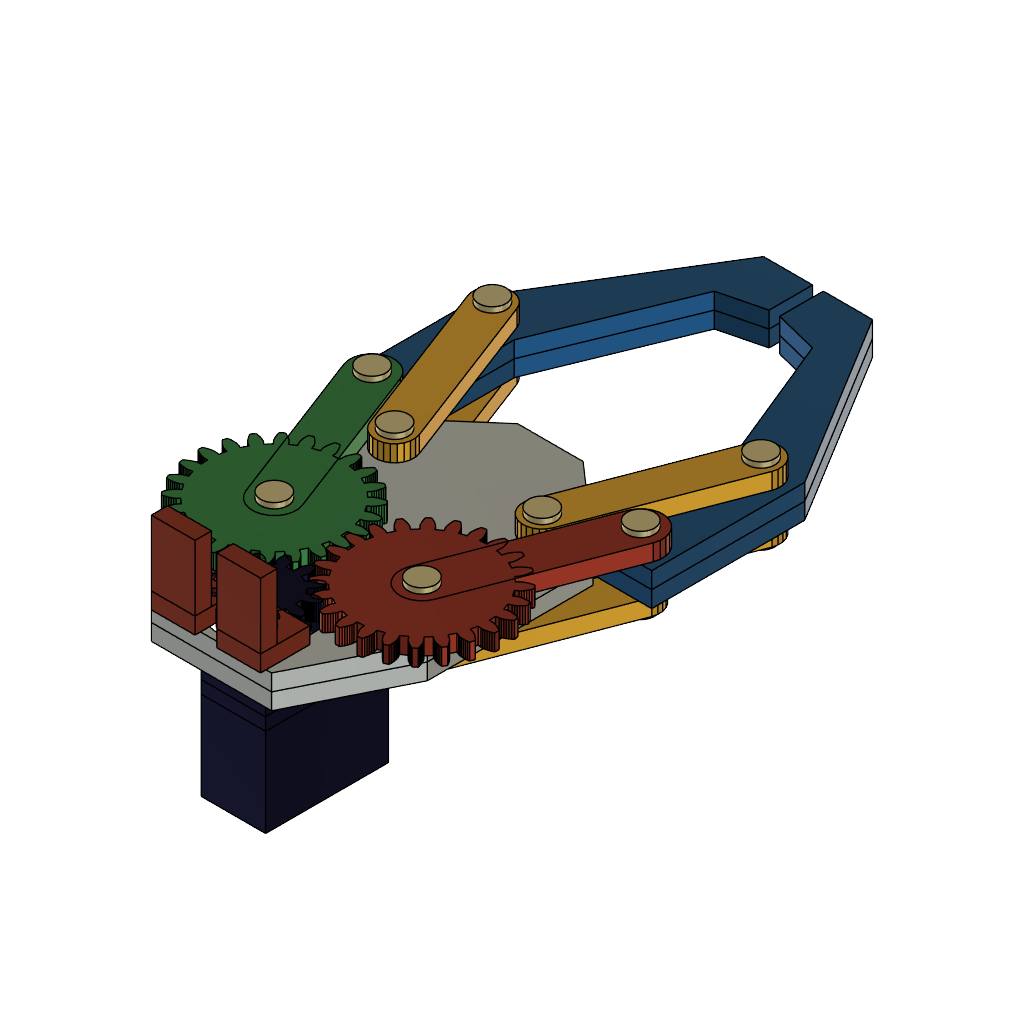
Robotic Gripper - SPARK PLUG recreation (Autodesk Fusion 360 design; units mm, degrees)
part number: 2026-11-17-09-29-30-338
part number: 2026-11-17-09-29-30-869
part number: 2026-11-17-09-29-32-026
part number: 2026-11-17-09-29-45-248
part number: 2026-11-17-09-29-48-497
part number: 2026-11-17-09-29-51-552
part number: 2026-11-17-09-29-54-288
part number: 2026-11-17-09-29-56-451
part number: 2026-11-17-09-29-59-617
part number: 2026-11-17-09-30-02-554
part number: 2026-11-17-09-30-05-354
part number: 2026-11-17-09-30-42-591
part number: 2026-11-17-09-30-51-417
part number: 2026-11-17-09-30-57-550
part number: 2026-11-17-09-31-01-790
part number: 2026-11-17-09-31-05-352
part number: 2026-11-17-09-31-09-246
part number: 2026-11-17-09-31-13-481
part number: 2026-11-17-09-31-18-259
part number: 2026-11-17-09-31-28-436
part number: 2026-11-17-09-31-31-446
part number: 2026-11-17-09-31-33-463
Autodesk Fusion 360 part; units mm, degrees
(part 1 of 3)
ref_plane "WorkPlane1" through (0, 0, -3) normal (0, 0, 1) x (1, 0, 0) in component "Frame - twin 3 mm plates"
sketch "Frame plate profile" plane through (0, 0, -3) normal (0, 0, 1) x (1, 0, 0) in component "Frame - twin 3 mm plates"
  line L0 (-11, -25) -> (11, -25)
  line L1 (11, -25) -> (20.5, -6)
  line L2 (20.5, -6) -> (20.5, 24.3)
  line L3 (20.5, 24.3) -> (6, 37)
  line L4 (6, 37) -> (-6, 37)
  line L5 (-6, 37) -> (-20.5, 24.3)
  line L6 (-20.5, 24.3) -> (-20.5, -6)
  line L7 (-20.5, -6) -> (-11, -25)
extrude "Frame plate" add sketch "Frame plate profile" along normal blind 3 makes body 1 in component "Frame - twin 3 mm plates"
sketch "Frame plate profile (1)" plane through (0, 0, 0) normal (0, 0, 1) x (1, 0, 0) in component "Frame - twin 3 mm plates"
  line L0 (-11, -25) -> (11, -25)
  line L1 (11, -25) -> (20.5, -6)
  line L2 (20.5, -6) -> (20.5, 24.3)
  line L3 (20.5, 24.3) -> (6, 37)
  line L4 (6, 37) -> (-6, 37)
  line L5 (-6, 37) -> (-20.5, 24.3)
  line L6 (-20.5, 24.3) -> (-20.5, -6)
  line L7 (-20.5, -6) -> (-11, -25)
extrude "Frame plate (1)" add sketch "Frame plate profile (1)" along normal blind 3 separate body makes body 2 in component "Frame - twin 3 mm plates"
ref_plane "WorkPlane2" through (0, 0, -3) normal (0, 0, 1) x (1, 0, 0) in component "Frame - twin 3 mm plates"
sketch "Pivot holes" plane through (0, 0, -3) normal (0, 0, 1) x (1, 0, 0) in component "Frame - twin 3 mm plates"
  circle A0 centre (-13.5, 0) radius 1.5
  circle A1 centre (13.5, 0) radius 1.5
  circle A2 centre (-13.5, 22) radius 1.5
  circle A3 centre (13.5, 22) radius 1.5
  circle A4 centre (-6, -21) radius 1.5
  circle A5 centre (6, -21) radius 1.5
extrude "Through holes" cut sketch "Pivot holes" along normal blind 6 bodies 1 2 in component "Frame - twin 3 mm plates"
ref_plane "WorkPlane3" through (0, 0, -3) normal (0, 0, 1) x (1, 0, 0) in component "Frame - twin 3 mm plates"
sketch "Motor clearance profile" plane through (0, 0, -3) normal (0, 0, 1) x (1, 0, 0) in component "Frame - twin 3 mm plates"
  circle A0 centre (0, -15.093) radius 8.5
extrude "Motor clearance" cut sketch "Motor clearance profile" along normal blind 6 bodies 1 2 in component "Frame - twin 3 mm plates"
ref_plane "WorkPlane1" through (0, 0, 3) normal (0, 0, 1) x (1, 0, 0) in component "Left 24T gear and crank"
sketch "24 tooth involute gear profile" plane through (0, 0, 3) normal (0, 0, 1) x (1, 0, 0) in component "Left 24T gear and crank"
  line L0 (-1.4453, -0.9707) -> (-0.8551, -1.0183)
  line L1 (-0.8551, -1.0183) -> (-0.5291, -0.995)
  line L2 (-0.5291, -0.995) -> (-0.2002, -0.9292)
  line L3 (-0.2002, -0.9292) -> (0.13, -0.8336)
  line L4 (0.13, -0.8336) -> (0.4604, -0.7126)
  line L5 (0.4604, -0.7126) -> (0.7905, -0.5684)
  line L6 (0.7905, -0.5684) -> (1.1195, -0.4024)
  line L7 (1.1195, -0.4024) -> (1.1195, 0.4024)
  line L8 (1.1195, 0.4024) -> (0.7905, 0.5684)
  line L9 (0.7905, 0.5684) -> (0.4604, 0.7126)
  line L10 (0.4604, 0.7126) -> (0.13, 0.8336)
  line L11 (0.13, 0.8336) -> (-0.2002, 0.9292)
  line L12 (-0.2002, 0.9292) -> (-0.5291, 0.995)
  line L13 (-0.5291, 0.995) -> (-0.8551, 1.0183)
  line L14 (-0.8551, 1.0183) -> (-1.4453, 0.9707)
  line L15 (-1.4453, 0.9707) -> (-1.6048, 2.1823)
  line L16 (-1.6048, 2.1823) -> (-1.0224, 2.2892)
  line L17 (-1.0224, 2.2892) -> (-0.7135, 2.396)
  line L18 (-0.7135, 2.396) -> (-0.4129, 2.5447)
  line L19 (-0.4129, 2.5447) -> (-0.1187, 2.7225)
  line L20 (-0.1187, 2.7225) -> (0.1692, 2.9249)
  line L21 (0.1692, 2.9249) -> (0.4507, 3.1496)
  line L22 (0.4507, 3.1496) -> (0.7255, 3.3951)
  line L23 (0.7255, 3.3951) -> (0.5172, 4.1725)
  line L24 (0.5172, 4.1725) -> (0.1565, 4.2477)
  line L25 (0.1565, 4.2477) -> (-0.1997, 4.3015)
  line L26 (-0.1997, 4.3015) -> (-0.5502, 4.3329)
  line L27 (-0.5502, 4.3329) -> (-0.8939, 4.3398)
  line L28 (-0.8939, 4.3398) -> (-1.2286, 4.3183)
  line L29 (-1.2286, 4.3183) -> (-1.5495, 4.2563)
  line L30 (-1.5495, 4.2563) -> (-2.1073, 4.0577)
  line L31 (-2.1073, 4.0577) -> (-2.5749, 5.1867)
  line L32 (-2.5749, 5.1867) -> (-2.04, 5.4406)
  line L33 (-2.04, 5.4406) -> (-1.7693, 5.6237)
  line L34 (-1.7693, 5.6237) -> (-1.5174, 5.8452)
  line L35 (-1.5174, 5.8452) -> (-1.2793, 6.093)
  line L36 (-1.2793, 6.093) -> (-1.0536, 6.3631)
  line L37 (-1.0536, 6.3631) -> (-0.8399, 6.653)
  line L38 (-0.8399, 6.653) -> (-0.638, 6.9612)
  line L39 (-0.638, 6.9612) -> (-1.0404, 7.6583)
  line L40 (-1.0404, 7.6583) -> (-1.4082, 7.6375)
  line L41 (-1.4082, 7.6375) -> (-1.7662, 7.5973)
  line L42 (-1.7662, 7.5973) -> (-2.1129, 7.5369)
  line L43 (-2.1129, 7.5369) -> (-2.4466, 7.4546)
  line L44 (-2.4466, 7.4546) -> (-2.7644, 7.3472)
  line L45 (-2.7644, 7.3472) -> (-3.0583, 7.2043)
  line L46 (-3.0583, 7.2043) -> (-3.5457, 6.868)
  line L47 (-3.5457, 6.868) -> (-4.2896, 7.8376)
  line L48 (-4.2896, 7.8376) -> (-3.8387, 8.2213)
  line L49 (-3.8387, 8.2213) -> (-3.6246, 8.4682)
  line L50 (-3.6246, 8.4682) -> (-3.4386, 8.7474)
  line L51 (-3.4386, 8.7474) -> (-3.2727, 9.0484)
  line L52 (-3.2727, 9.0484) -> (-3.1246, 9.3676)
  line L53 (-3.1246, 9.3676) -> (-2.9932, 9.703)
  line L54 (-2.9932, 9.703) -> (-2.8779, 10.0529)
  line L55 (-2.8779, 10.0529) -> (-3.4471, 10.6221)
  line L56 (-3.4471, 10.6221) -> (-3.797, 10.5068)
  line L57 (-3.797, 10.5068) -> (-4.1324, 10.3754)
  line L58 (-4.1324, 10.3754) -> (-4.4516, 10.2273)
  line L59 (-4.4516, 10.2273) -> (-4.7526, 10.0614)
  line L60 (-4.7526, 10.0614) -> (-5.0318, 9.8754)
  line L61 (-5.0318, 9.8754) -> (-5.2787, 9.6613)
  line L62 (-5.2787, 9.6613) -> (-5.6624, 9.2104)
  line L63 (-5.6624, 9.2104) -> (-6.632, 9.9543)
  line L64 (-6.632, 9.9543) -> (-6.2957, 10.4417)
  line L65 (-6.2957, 10.4417) -> (-6.1528, 10.7356)
  line L66 (-6.1528, 10.7356) -> (-6.0454, 11.0534)
  line L67 (-6.0454, 11.0534) -> (-5.9631, 11.3871)
  line L68 (-5.9631, 11.3871) -> (-5.9027, 11.7338)
  line L69 (-5.9027, 11.7338) -> (-5.8625, 12.0918)
  line L70 (-5.8625, 12.0918) -> (-5.8417, 12.4596)
  line L71 (-5.8417, 12.4596) -> (-6.5388, 12.862)
  line L72 (-6.5388, 12.862) -> (-6.847, 12.6601)
  line L73 (-6.847, 12.6601) -> (-7.1369, 12.4464)
  line L74 (-7.1369, 12.4464) -> (-7.407, 12.2207)
  line L75 (-7.407, 12.2207) -> (-7.6548, 11.9826)
  line L76 (-7.6548, 11.9826) -> (-7.8763, 11.7307)
  line L77 (-7.8763, 11.7307) -> (-8.0594, 11.46)
  line L78 (-8.0594, 11.46) -> (-8.3133, 10.9251)
  line L79 (-8.3133, 10.9251) -> (-9.4423, 11.3927)
  line L80 (-9.4423, 11.3927) -> (-9.2437, 11.9505)
  line L81 (-9.2437, 11.9505) -> (-9.1817, 12.2714)
  line L82 (-9.1817, 12.2714) -> (-9.1602, 12.6061)
  line L83 (-9.1602, 12.6061) -> (-9.1671, 12.9498)
  line L84 (-9.1671, 12.9498) -> (-9.1985, 13.3003)
  line L85 (-9.1985, 13.3003) -> (-9.2523, 13.6565)
  line L86 (-9.2523, 13.6565) -> (-9.3275, 14.0172)
  line L87 (-9.3275, 14.0172) -> (-10.1049, 14.2255)
  line L88 (-10.1049, 14.2255) -> (-10.3504, 13.9507)
  line L89 (-10.3504, 13.9507) -> (-10.5751, 13.6692)
  line L90 (-10.5751, 13.6692) -> (-10.7775, 13.3813)
  line L91 (-10.7775, 13.3813) -> (-10.9553, 13.0871)
  line L92 (-10.9553, 13.0871) -> (-11.104, 12.7865)
  line L93 (-11.104, 12.7865) -> (-11.2108, 12.4776)
  line L94 (-11.2108, 12.4776) -> (-11.3177, 11.8952)
  line L95 (-11.3177, 11.8952) -> (-12.5293, 12.0547)
  line L96 (-12.5293, 12.0547) -> (-12.4817, 12.6449)
  line L97 (-12.4817, 12.6449) -> (-12.505, 12.9709)
  line L98 (-12.505, 12.9709) -> (-12.5708, 13.2998)
  line L99 (-12.5708, 13.2998) -> (-12.6664, 13.63)
  line L100 (-12.6664, 13.63) -> (-12.7874, 13.9604)
  line L101 (-12.7874, 13.9604) -> (-12.9316, 14.2905)
  line L102 (-12.9316, 14.2905) -> (-13.0976, 14.6195)
  line L103 (-13.0976, 14.6195) -> (-13.9024, 14.6195)
  line L104 (-13.9024, 14.6195) -> (-14.0684, 14.2905)
  line L105 (-14.0684, 14.2905) -> (-14.2126, 13.9604)
  line L106 (-14.2126, 13.9604) -> (-14.3336, 13.63)
  line L107 (-14.3336, 13.63) -> (-14.4292, 13.2998)
  line L108 (-14.4292, 13.2998) -> (-14.495, 12.9709)
  line L109 (-14.495, 12.9709) -> (-14.5183, 12.6449)
  line L110 (-14.5183, 12.6449) -> (-14.4707, 12.0547)
  line L111 (-14.4707, 12.0547) -> (-15.6823, 11.8952)
  line L112 (-15.6823, 11.8952) -> (-15.7892, 12.4776)
  line L113 (-15.7892, 12.4776) -> (-15.896, 12.7865)
  line L114 (-15.896, 12.7865) -> (-16.0447, 13.0871)
  line L115 (-16.0447, 13.0871) -> (-16.2225, 13.3813)
  line L116 (-16.2225, 13.3813) -> (-16.4249, 13.6692)
  line L117 (-16.4249, 13.6692) -> (-16.6496, 13.9507)
  line L118 (-16.6496, 13.9507) -> (-16.8951, 14.2255)
  line L119 (-16.8951, 14.2255) -> (-17.6725, 14.0172)
  line L120 (-17.6725, 14.0172) -> (-17.7477, 13.6565)
  line L121 (-17.7477, 13.6565) -> (-17.8015, 13.3003)
  line L122 (-17.8015, 13.3003) -> (-17.8329, 12.9498)
  line L123 (-17.8329, 12.9498) -> (-17.8398, 12.6061)
  line L124 (-17.8398, 12.6061) -> (-17.8183, 12.2714)
  line L125 (-17.8183, 12.2714) -> (-17.7563, 11.9505)
  line L126 (-17.7563, 11.9505) -> (-17.5577, 11.3927)
  line L127 (-17.5577, 11.3927) -> (-18.6867, 10.9251)
  line L128 (-18.6867, 10.9251) -> (-18.9406, 11.46)
  line L129 (-18.9406, 11.46) -> (-19.1237, 11.7307)
  line L130 (-19.1237, 11.7307) -> (-19.3452, 11.9826)
  line L131 (-19.3452, 11.9826) -> (-19.593, 12.2207)
  line L132 (-19.593, 12.2207) -> (-19.8631, 12.4464)
  line L133 (-19.8631, 12.4464) -> (-20.153, 12.6601)
  line L134 (-20.153, 12.6601) -> (-20.4612, 12.862)
  line L135 (-20.4612, 12.862) -> (-21.1583, 12.4596)
  line L136 (-21.1583, 12.4596) -> (-21.1375, 12.0918)
  line L137 (-21.1375, 12.0918) -> (-21.0973, 11.7338)
  line L138 (-21.0973, 11.7338) -> (-21.0369, 11.3871)
  line L139 (-21.0369, 11.3871) -> (-20.9546, 11.0534)
  line L140 (-20.9546, 11.0534) -> (-20.8472, 10.7356)
  line L141 (-20.8472, 10.7356) -> (-20.7043, 10.4417)
  line L142 (-20.7043, 10.4417) -> (-20.368, 9.9543)
  line L143 (-20.368, 9.9543) -> (-21.3376, 9.2104)
  line L144 (-21.3376, 9.2104) -> (-21.7213, 9.6613)
  line L145 (-21.7213, 9.6613) -> (-21.9682, 9.8754)
  line L146 (-21.9682, 9.8754) -> (-22.2474, 10.0614)
  line L147 (-22.2474, 10.0614) -> (-22.5484, 10.2273)
  line L148 (-22.5484, 10.2273) -> (-22.8676, 10.3754)
  line L149 (-22.8676, 10.3754) -> (-23.203, 10.5068)
  line L150 (-23.203, 10.5068) -> (-23.5529, 10.6221)
  line L151 (-23.5529, 10.6221) -> (-24.1221, 10.0529)
  line L152 (-24.1221, 10.0529) -> (-24.0068, 9.703)
  line L153 (-24.0068, 9.703) -> (-23.8754, 9.3676)
  line L154 (-23.8754, 9.3676) -> (-23.7273, 9.0484)
  line L155 (-23.7273, 9.0484) -> (-23.5614, 8.7474)
  line L156 (-23.5614, 8.7474) -> (-23.3754, 8.4682)
  line L157 (-23.3754, 8.4682) -> (-23.1613, 8.2213)
  line L158 (-23.1613, 8.2213) -> (-22.7104, 7.8376)
  line L159 (-22.7104, 7.8376) -> (-23.4543, 6.868)
  line L160 (-23.4543, 6.868) -> (-23.9417, 7.2043)
  line L161 (-23.9417, 7.2043) -> (-24.2356, 7.3472)
  line L162 (-24.2356, 7.3472) -> (-24.5534, 7.4546)
  line L163 (-24.5534, 7.4546) -> (-24.8871, 7.5369)
  line L164 (-24.8871, 7.5369) -> (-25.2338, 7.5973)
  line L165 (-25.2338, 7.5973) -> (-25.5918, 7.6375)
  line L166 (-25.5918, 7.6375) -> (-25.9596, 7.6583)
  line L167 (-25.9596, 7.6583) -> (-26.362, 6.9612)
  line L168 (-26.362, 6.9612) -> (-26.1601, 6.653)
  line L169 (-26.1601, 6.653) -> (-25.9464, 6.3631)
  line L170 (-25.9464, 6.3631) -> (-25.7207, 6.093)
  line L171 (-25.7207, 6.093) -> (-25.4826, 5.8452)
  line L172 (-25.4826, 5.8452) -> (-25.2307, 5.6237)
  line L173 (-25.2307, 5.6237) -> (-24.96, 5.4406)
  line L174 (-24.96, 5.4406) -> (-24.4251, 5.1867)
  line L175 (-24.4251, 5.1867) -> (-24.8927, 4.0577)
  line L176 (-24.8927, 4.0577) -> (-25.4505, 4.2563)
  line L177 (-25.4505, 4.2563) -> (-25.7714, 4.3183)
  line L178 (-25.7714, 4.3183) -> (-26.1061, 4.3398)
  line L179 (-26.1061, 4.3398) -> (-26.4498, 4.3329)
  line L180 (-26.4498, 4.3329) -> (-26.8003, 4.3015)
  line L181 (-26.8003, 4.3015) -> (-27.1565, 4.2477)
  line L182 (-27.1565, 4.2477) -> (-27.5172, 4.1725)
  line L183 (-27.5172, 4.1725) -> (-27.7255, 3.3951)
  line L184 (-27.7255, 3.3951) -> (-27.4507, 3.1496)
  line L185 (-27.4507, 3.1496) -> (-27.1692, 2.9249)
  line L186 (-27.1692, 2.9249) -> (-26.8813, 2.7225)
  line L187 (-26.8813, 2.7225) -> (-26.5871, 2.5447)
  line L188 (-26.5871, 2.5447) -> (-26.2865, 2.396)
  line L189 (-26.2865, 2.396) -> (-25.9776, 2.2892)
  line L190 (-25.9776, 2.2892) -> (-25.3952, 2.1823)
  line L191 (-25.3952, 2.1823) -> (-25.5547, 0.9707)
  line L192 (-25.5547, 0.9707) -> (-26.1449, 1.0183)
  line L193 (-26.1449, 1.0183) -> (-26.4709, 0.995)
  line L194 (-26.4709, 0.995) -> (-26.7998, 0.9292)
  line L195 (-26.7998, 0.9292) -> (-27.13, 0.8336)
  line L196 (-27.13, 0.8336) -> (-27.4604, 0.7126)
  line L197 (-27.4604, 0.7126) -> (-27.7905, 0.5684)
  line L198 (-27.7905, 0.5684) -> (-28.1195, 0.4024)
  line L199 (-28.1195, 0.4024) -> (-28.1195, -0.4024)
  line L200 (-28.1195, -0.4024) -> (-27.7905, -0.5684)
  line L201 (-27.7905, -0.5684) -> (-27.4604, -0.7126)
  line L202 (-27.4604, -0.7126) -> (-27.13, -0.8336)
  line L203 (-27.13, -0.8336) -> (-26.7998, -0.9292)
  line L204 (-26.7998, -0.9292) -> (-26.4709, -0.995)
  line L205 (-26.4709, -0.995) -> (-26.1449, -1.0183)
  line L206 (-26.1449, -1.0183) -> (-25.5547, -0.9707)
  line L207 (-25.5547, -0.9707) -> (-25.3952, -2.1823)
  line L208 (-25.3952, -2.1823) -> (-25.9776, -2.2892)
  line L209 (-25.9776, -2.2892) -> (-26.2865, -2.396)
  line L210 (-26.2865, -2.396) -> (-26.5871, -2.5447)
  line L211 (-26.5871, -2.5447) -> (-26.8813, -2.7225)
  line L212 (-26.8813, -2.7225) -> (-27.1692, -2.9249)
  line L213 (-27.1692, -2.9249) -> (-27.4507, -3.1496)
  line L214 (-27.4507, -3.1496) -> (-27.7255, -3.3951)
  line L215 (-27.7255, -3.3951) -> (-27.5172, -4.1725)
  line L216 (-27.5172, -4.1725) -> (-27.1565, -4.2477)
  line L217 (-27.1565, -4.2477) -> (-26.8003, -4.3015)
  line L218 (-26.8003, -4.3015) -> (-26.4498, -4.3329)
  line L219 (-26.4498, -4.3329) -> (-26.1061, -4.3398)
  line L220 (-26.1061, -4.3398) -> (-25.7714, -4.3183)
  line L221 (-25.7714, -4.3183) -> (-25.4505, -4.2563)
  line L222 (-25.4505, -4.2563) -> (-24.8927, -4.0577)
  line L223 (-24.8927, -4.0577) -> (-24.4251, -5.1867)
  line L224 (-24.4251, -5.1867) -> (-24.96, -5.4406)
  line L225 (-24.96, -5.4406) -> (-25.2307, -5.6237)
  line L226 (-25.2307, -5.6237) -> (-25.4826, -5.8452)
  line L227 (-25.4826, -5.8452) -> (-25.7207, -6.093)
  line L228 (-25.7207, -6.093) -> (-25.9464, -6.3631)
  line L229 (-25.9464, -6.3631) -> (-26.1601, -6.653)
  line L230 (-26.1601, -6.653) -> (-26.362, -6.9612)
  line L231 (-26.362, -6.9612) -> (-25.9596, -7.6583)
  line L232 (-25.9596, -7.6583) -> (-25.5918, -7.6375)
  line L233 (-25.5918, -7.6375) -> (-25.2338, -7.5973)
  line L234 (-25.2338, -7.5973) -> (-24.8871, -7.5369)
  line L235 (-24.8871, -7.5369) -> (-24.5534, -7.4546)
  line L236 (-24.5534, -7.4546) -> (-24.2356, -7.3472)
  line L237 (-24.2356, -7.3472) -> (-23.9417, -7.2043)
  line L238 (-23.9417, -7.2043) -> (-23.4543, -6.868)
  line L239 (-23.4543, -6.868) -> (-22.7104, -7.8376)
  line L240 (-22.7104, -7.8376) -> (-23.1613, -8.2213)
  line L241 (-23.1613, -8.2213) -> (-23.3754, -8.4682)
  line L242 (-23.3754, -8.4682) -> (-23.5614, -8.7474)
  line L243 (-23.5614, -8.7474) -> (-23.7273, -9.0484)
  line L244 (-23.7273, -9.0484) -> (-23.8754, -9.3676)
  line L245 (-23.8754, -9.3676) -> (-24.0068, -9.703)
  line L246 (-24.0068, -9.703) -> (-24.1221, -10.0529)
  line L247 (-24.1221, -10.0529) -> (-23.5529, -10.6221)
  line L248 (-23.5529, -10.6221) -> (-23.203, -10.5068)
  line L249 (-23.203, -10.5068) -> (-22.8676, -10.3754)
  line L250 (-22.8676, -10.3754) -> (-22.5484, -10.2273)
  line L251 (-22.5484, -10.2273) -> (-22.2474, -10.0614)
  line L252 (-22.2474, -10.0614) -> (-21.9682, -9.8754)
  line L253 (-21.9682, -9.8754) -> (-21.7213, -9.6613)
  line L254 (-21.7213, -9.6613) -> (-21.3376, -9.2104)
  line L255 (-21.3376, -9.2104) -> (-20.368, -9.9543)
  line L256 (-20.368, -9.9543) -> (-20.7043, -10.4417)
  line L257 (-20.7043, -10.4417) -> (-20.8472, -10.7356)
  line L258 (-20.8472, -10.7356) -> (-20.9546, -11.0534)
  line L259 (-20.9546, -11.0534) -> (-21.0369, -11.3871)
  line L260 (-21.0369, -11.3871) -> (-21.0973, -11.7338)
  line L261 (-21.0973, -11.7338) -> (-21.1375, -12.0918)
  line L262 (-21.1375, -12.0918) -> (-21.1583, -12.4596)
  line L263 (-21.1583, -12.4596) -> (-20.4612, -12.862)
  line L264 (-20.4612, -12.862) -> (-20.153, -12.6601)
  line L265 (-20.153, -12.6601) -> (-19.8631, -12.4464)
  line L266 (-19.8631, -12.4464) -> (-19.593, -12.2207)
  line L267 (-19.593, -12.2207) -> (-19.3452, -11.9826)
  line L268 (-19.3452, -11.9826) -> (-19.1237, -11.7307)
  line L269 (-19.1237, -11.7307) -> (-18.9406, -11.46)
  line L270 (-18.9406, -11.46) -> (-18.6867, -10.9251)
  line L271 (-18.6867, -10.9251) -> (-17.5577, -11.3927)
  line L272 (-17.5577, -11.3927) -> (-17.7563, -11.9505)
  line L273 (-17.7563, -11.9505) -> (-17.8183, -12.2714)
  line L274 (-17.8183, -12.2714) -> (-17.8398, -12.6061)
  line L275 (-17.8398, -12.6061) -> (-17.8329, -12.9498)
  line L276 (-17.8329, -12.9498) -> (-17.8015, -13.3003)
  line L277 (-17.8015, -13.3003) -> (-17.7477, -13.6565)
  line L278 (-17.7477, -13.6565) -> (-17.6725, -14.0172)
  line L279 (-17.6725, -14.0172) -> (-16.8951, -14.2255)
  line L280 (-16.8951, -14.2255) -> (-16.6496, -13.9507)
  line L281 (-16.6496, -13.9507) -> (-16.4249, -13.6692)
  line L282 (-16.4249, -13.6692) -> (-16.2225, -13.3813)
  line L283 (-16.2225, -13.3813) -> (-16.0447, -13.0871)
  line L284 (-16.0447, -13.0871) -> (-15.896, -12.7865)
  line L285 (-15.896, -12.7865) -> (-15.7892, -12.4776)
  line L286 (-15.7892, -12.4776) -> (-15.6823, -11.8952)
  line L287 (-15.6823, -11.8952) -> (-14.4707, -12.0547)
  line L288 (-14.4707, -12.0547) -> (-14.5183, -12.6449)
  line L289 (-14.5183, -12.6449) -> (-14.495, -12.9709)
  line L290 (-14.495, -12.9709) -> (-14.4292, -13.2998)
  line L291 (-14.4292, -13.2998) -> (-14.3336, -13.63)
  line L292 (-14.3336, -13.63) -> (-14.2126, -13.9604)
  line L293 (-14.2126, -13.9604) -> (-14.0684, -14.2905)
  line L294 (-14.0684, -14.2905) -> (-13.9024, -14.6195)
  line L295 (-13.9024, -14.6195) -> (-13.0976, -14.6195)
  line L296 (-13.0976, -14.6195) -> (-12.9316, -14.2905)
  line L297 (-12.9316, -14.2905) -> (-12.7874, -13.9604)
  line L298 (-12.7874, -13.9604) -> (-12.6664, -13.63)
  line L299 (-12.6664, -13.63) -> (-12.5708, -13.2998)
  line L300 (-12.5708, -13.2998) -> (-12.505, -12.9709)
  line L301 (-12.505, -12.9709) -> (-12.4817, -12.6449)
  line L302 (-12.4817, -12.6449) -> (-12.5293, -12.0547)
  line L303 (-12.5293, -12.0547) -> (-11.3177, -11.8952)
  line L304 (-11.3177, -11.8952) -> (-11.2108, -12.4776)
  line L305 (-11.2108, -12.4776) -> (-11.104, -12.7865)
  line L306 (-11.104, -12.7865) -> (-10.9553, -13.0871)
  line L307 (-10.9553, -13.0871) -> (-10.7775, -13.3813)
  line L308 (-10.7775, -13.3813) -> (-10.5751, -13.6692)
  line L309 (-10.5751, -13.6692) -> (-10.3504, -13.9507)
  line L310 (-10.3504, -13.9507) -> (-10.1049, -14.2255)
  line L311 (-10.1049, -14.2255) -> (-9.3275, -14.0172)
  line L312 (-9.3275, -14.0172) -> (-9.2523, -13.6565)
  line L313 (-9.2523, -13.6565) -> (-9.1985, -13.3003)
  line L314 (-9.1985, -13.3003) -> (-9.1671, -12.9498)
  line L315 (-9.1671, -12.9498) -> (-9.1602, -12.6061)
  line L316 (-9.1602, -12.6061) -> (-9.1817, -12.2714)
  line L317 (-9.1817, -12.2714) -> (-9.2437, -11.9505)
  line L318 (-9.2437, -11.9505) -> (-9.4423, -11.3927)
  line L319 (-9.4423, -11.3927) -> (-8.3133, -10.9251)
  line L320 (-8.3133, -10.9251) -> (-8.0594, -11.46)
  line L321 (-8.0594, -11.46) -> (-7.8763, -11.7307)
  line L322 (-7.8763, -11.7307) -> (-7.6548, -11.9826)
  line L323 (-7.6548, -11.9826) -> (-7.407, -12.2207)
  line L324 (-7.407, -12.2207) -> (-7.1369, -12.4464)
  line L325 (-7.1369, -12.4464) -> (-6.847, -12.6601)
  line L326 (-6.847, -12.6601) -> (-6.5388, -12.862)
  line L327 (-6.5388, -12.862) -> (-5.8417, -12.4596)
  line L328 (-5.8417, -12.4596) -> (-5.8625, -12.0918)
  line L329 (-5.8625, -12.0918) -> (-5.9027, -11.7338)
  line L330 (-5.9027, -11.7338) -> (-5.9631, -11.3871)
  line L331 (-5.9631, -11.3871) -> (-6.0454, -11.0534)
  line L332 (-6.0454, -11.0534) -> (-6.1528, -10.7356)
  line L333 (-6.1528, -10.7356) -> (-6.2957, -10.4417)
  line L334 (-6.2957, -10.4417) -> (-6.632, -9.9543)
  line L335 (-6.632, -9.9543) -> (-5.6624, -9.2104)
  line L336 (-5.6624, -9.2104) -> (-5.2787, -9.6613)
  line L337 (-5.2787, -9.6613) -> (-5.0318, -9.8754)
  line L338 (-5.0318, -9.8754) -> (-4.7526, -10.0614)
  line L339 (-4.7526, -10.0614) -> (-4.4516, -10.2273)
  line L340 (-4.4516, -10.2273) -> (-4.1324, -10.3754)
  line L341 (-4.1324, -10.3754) -> (-3.797, -10.5068)
  line L342 (-3.797, -10.5068) -> (-3.4471, -10.6221)
  line L343 (-3.4471, -10.6221) -> (-2.8779, -10.0529)
  line L344 (-2.8779, -10.0529) -> (-2.9932, -9.703)
  line L345 (-2.9932, -9.703) -> (-3.1246, -9.3676)
  line L346 (-3.1246, -9.3676) -> (-3.2727, -9.0484)
  line L347 (-3.2727, -9.0484) -> (-3.4386, -8.7474)
  line L348 (-3.4386, -8.7474) -> (-3.6246, -8.4682)
  line L349 (-3.6246, -8.4682) -> (-3.8387, -8.2213)
  line L350 (-3.8387, -8.2213) -> (-4.2896, -7.8376)
  line L351 (-4.2896, -7.8376) -> (-3.5457, -6.868)
  line L352 (-3.5457, -6.868) -> (-3.0583, -7.2043)
  line L353 (-3.0583, -7.2043) -> (-2.7644, -7.3472)
  line L354 (-2.7644, -7.3472) -> (-2.4466, -7.4546)
  line L355 (-2.4466, -7.4546) -> (-2.1129, -7.5369)
  line L356 (-2.1129, -7.5369) -> (-1.7662, -7.5973)
  line L357 (-1.7662, -7.5973) -> (-1.4082, -7.6375)
  line L358 (-1.4082, -7.6375) -> (-1.0404, -7.6583)
  line L359 (-1.0404, -7.6583) -> (-0.638, -6.9612)
  line L360 (-0.638, -6.9612) -> (-0.8399, -6.653)
  line L361 (-0.8399, -6.653) -> (-1.0536, -6.3631)
  line L362 (-1.0536, -6.3631) -> (-1.2793, -6.093)
  line L363 (-1.2793, -6.093) -> (-1.5174, -5.8452)
  line L364 (-1.5174, -5.8452) -> (-1.7693, -5.6237)
  line L365 (-1.7693, -5.6237) -> (-2.04, -5.4406)
  line L366 (-2.04, -5.4406) -> (-2.5749, -5.1867)
  line L367 (-2.5749, -5.1867) -> (-2.1073, -4.0577)
  line L368 (-2.1073, -4.0577) -> (-1.5495, -4.2563)
  line L369 (-1.5495, -4.2563) -> (-1.2286, -4.3183)
  line L370 (-1.2286, -4.3183) -> (-0.8939, -4.3398)
  line L371 (-0.8939, -4.3398) -> (-0.5502, -4.3329)
  line L372 (-0.5502, -4.3329) -> (-0.1997, -4.3015)
  line L373 (-0.1997, -4.3015) -> (0.1565, -4.2477)
  line L374 (0.1565, -4.2477) -> (0.5172, -4.1725)
  line L375 (0.5172, -4.1725) -> (0.7255, -3.3951)
  line L376 (0.7255, -3.3951) -> (0.4507, -3.1496)
  line L377 (0.4507, -3.1496) -> (0.1692, -2.9249)
  line L378 (0.1692, -2.9249) -> (-0.1187, -2.7225)
  line L379 (-0.1187, -2.7225) -> (-0.4129, -2.5447)
  line L380 (-0.4129, -2.5447) -> (-0.7135, -2.396)
  line L381 (-0.7135, -2.396) -> (-1.0224, -2.2892)
  line L382 (-1.0224, -2.2892) -> (-1.6048, -2.1823)
  line L383 (-1.6048, -2.1823) -> (-1.4453, -0.9707)
extrude "24 tooth involute gear" add sketch "24 tooth involute gear profile" along normal blind 3 separate body makes body 3 in component "Left 24T gear and crank"
ref_plane "WorkPlane2" through (0, 0, 3) normal (0, 0, 1) x (1, 0, 0) in component "Left 24T gear and crank"
sketch "31 mm crank profile" plane through (0, 0, 3) normal (0, 0, 1) x (1, 0, 0) in component "Left 24T gear and crank"
  line L0 (-22.9759, 29.786) -> (-23.537, 30.6667)
  line L1 (-23.537, 30.6667) -> (-24.3069, 31.3721)
  line L2 (-24.3069, 31.3721) -> (-25.2331, 31.8543)
  line L3 (-25.2331, 31.8543) -> (-26.2525, 32.0803)
  line L4 (-26.2525, 32.0803) -> (-27.2958, 32.0348)
  line L5 (-27.2958, 32.0348) -> (-28.2916, 31.7208)
  line L6 (-28.2916, 31.7208) -> (-29.1723, 31.1597)
  line L7 (-29.1723, 31.1597) -> (-29.8778, 30.3898)
  line L8 (-29.8778, 30.3898) -> (-30.3599, 29.4636)
  line L9 (-30.3599, 29.4636) -> (-30.5859, 28.4442)
  line L10 (-30.5859, 28.4442) -> (-30.5404, 27.4009)
  line L11 (-30.5404, 27.4009) -> (-30.2264, 26.4051)
  line L12 (-30.2264, 26.4051) -> (-17.1252, -1.6905)
  line L13 (-17.1252, -1.6905) -> (-16.5642, -2.5712)
  line L14 (-16.5642, -2.5712) -> (-15.7943, -3.2766)
  line L15 (-15.7943, -3.2766) -> (-14.8681, -3.7588)
  line L16 (-14.8681, -3.7588) -> (-13.8486, -3.9848)
  line L17 (-13.8486, -3.9848) -> (-12.8054, -3.9392)
  line L18 (-12.8054, -3.9392) -> (-11.8095, -3.6252)
  line L19 (-11.8095, -3.6252) -> (-10.9288, -3.0642)
  line L20 (-10.9288, -3.0642) -> (-10.2234, -2.2943)
  line L21 (-10.2234, -2.2943) -> (-9.7412, -1.3681)
  line L22 (-9.7412, -1.3681) -> (-9.5152, -0.3486)
  line L23 (-9.5152, -0.3486) -> (-9.5608, 0.6946)
  line L24 (-9.5608, 0.6946) -> (-9.8748, 1.6905)
  line L25 (-9.8748, 1.6905) -> (-22.9759, 29.786)
extrude "31 mm crank" add sketch "31 mm crank profile" along normal blind 3 separate body makes body 4 in component "Left 24T gear and crank"
ref_plane "WorkPlane3" through (0, 0, 3) normal (0, 0, 1) x (1, 0, 0) in component "Left 24T gear and crank"
sketch "Pivot holes (2)" plane through (0, 0, 3) normal (0, 0, 1) x (1, 0, 0) in component "Left 24T gear and crank"
  circle A0 centre (-13.5, 0) radius 1.5
  circle A1 centre (-26.6012, 28.0955) radius 1.5
extrude "Through holes'" cut sketch "Pivot holes (2)" along normal blind 3 bodies 3 4 in component "Left 24T gear and crank"
sketch "Left gear pivot axis" plane through (0, 0, 0) normal (0, 0, 1) x (1, 0, 0) in component "Frame - twin 3 mm plates"
  point P0 (-13.5, 0)
ref_plane "WorkPlane1" through (0, 0, 3) normal (0, 0, 1) x (1, 0, 0) in component "Left parallel links"
sketch "31 mm parallel link profile" plane through (0, 0, 3) normal (0, 0, 1) x (1, 0, 0) in component "Left parallel links"
  line L0 (-23.4291, 51.5747) -> (-23.92, 52.3453)
  line L1 (-23.92, 52.3453) -> (-24.5936, 52.9626)
  line L2 (-24.5936, 52.9626) -> (-25.4041, 53.3845)
  line L3 (-25.4041, 53.3845) -> (-26.2961, 53.5822)
  line L4 (-26.2961, 53.5822) -> (-27.2089, 53.5424)
  line L5 (-27.2089, 53.5424) -> (-28.0803, 53.2676)
  line L6 (-28.0803, 53.2676) -> (-28.8509, 52.7767)
  line L7 (-28.8509, 52.7767) -> (-29.4682, 52.1031)
  line L8 (-29.4682, 52.1031) -> (-29.8901, 51.2926)
  line L9 (-29.8901, 51.2926) -> (-30.0878, 50.4006)
  line L10 (-30.0878, 50.4006) -> (-30.048, 49.4878)
  line L11 (-30.048, 49.4878) -> (-29.7732, 48.6164)
  line L12 (-29.7732, 48.6164) -> (-16.6721, 20.5208)
  line L13 (-16.6721, 20.5208) -> (-16.1812, 19.7502)
  line L14 (-16.1812, 19.7502) -> (-15.5075, 19.133)
  line L15 (-15.5075, 19.133) -> (-14.6971, 18.7111)
  line L16 (-14.6971, 18.7111) -> (-13.805, 18.5133)
  line L17 (-13.805, 18.5133) -> (-12.8922, 18.5532)
  line L18 (-12.8922, 18.5532) -> (-12.0208, 18.8279)
  line L19 (-12.0208, 18.8279) -> (-11.2502, 19.3188)
  line L20 (-11.2502, 19.3188) -> (-10.633, 19.9925)
  line L21 (-10.633, 19.9925) -> (-10.2111, 20.8029)
  line L22 (-10.2111, 20.8029) -> (-10.0133, 21.695)
  line L23 (-10.0133, 21.695) -> (-10.0532, 22.6078)
  line L24 (-10.0532, 22.6078) -> (-10.3279, 23.4792)
  line L25 (-10.3279, 23.4792) -> (-23.4291, 51.5747)
extrude "31 mm parallel link" add sketch "31 mm parallel link profile" along normal blind 3 separate body makes body 5 in component "Left parallel links"
ref_plane "WorkPlane2" through (0, 0, 3) normal (0, 0, 1) x (1, 0, 0) in component "Left parallel links"
sketch "Pivot holes (3)" plane through (0, 0, 3) normal (0, 0, 1) x (1, 0, 0) in component "Left parallel links"
  circle A0 centre (-13.5, 22) radius 1.5
  circle A1 centre (-26.6012, 50.0955) radius 1.5
extrude "Through holes''" cut sketch "Pivot holes (3)" along normal blind 3 bodies 5 in component "Left parallel links"
ref_plane "WorkPlane3" through (0, 0, -6) normal (0, 0, 1) x (1, 0, 0) in component "Left parallel links"
sketch "31 mm parallel link profile (1)" plane through (0, 0, -6) normal (0, 0, 1) x (1, 0, 0) in component "Left parallel links"
  line L0 (-23.4291, 51.5747) -> (-23.92, 52.3453)
  line L1 (-23.92, 52.3453) -> (-24.5936, 52.9626)
  line L2 (-24.5936, 52.9626) -> (-25.4041, 53.3845)
  line L3 (-25.4041, 53.3845) -> (-26.2961, 53.5822)
  line L4 (-26.2961, 53.5822) -> (-27.2089, 53.5424)
  line L5 (-27.2089, 53.5424) -> (-28.0803, 53.2676)
  line L6 (-28.0803, 53.2676) -> (-28.8509, 52.7767)
  line L7 (-28.8509, 52.7767) -> (-29.4682, 52.1031)
  line L8 (-29.4682, 52.1031) -> (-29.8901, 51.2926)
  line L9 (-29.8901, 51.2926) -> (-30.0878, 50.4006)
  line L10 (-30.0878, 50.4006) -> (-30.048, 49.4878)
  line L11 (-30.048, 49.4878) -> (-29.7732, 48.6164)
  line L12 (-29.7732, 48.6164) -> (-16.6721, 20.5208)
  line L13 (-16.6721, 20.5208) -> (-16.1812, 19.7502)
  line L14 (-16.1812, 19.7502) -> (-15.5075, 19.133)
  line L15 (-15.5075, 19.133) -> (-14.6971, 18.7111)
  line L16 (-14.6971, 18.7111) -> (-13.805, 18.5133)
  line L17 (-13.805, 18.5133) -> (-12.8922, 18.5532)
  line L18 (-12.8922, 18.5532) -> (-12.0208, 18.8279)
  line L19 (-12.0208, 18.8279) -> (-11.2502, 19.3188)
  line L20 (-11.2502, 19.3188) -> (-10.633, 19.9925)
  line L21 (-10.633, 19.9925) -> (-10.2111, 20.8029)
  line L22 (-10.2111, 20.8029) -> (-10.0133, 21.695)
  line L23 (-10.0133, 21.695) -> (-10.0532, 22.6078)
  line L24 (-10.0532, 22.6078) -> (-10.3279, 23.4792)
  line L25 (-10.3279, 23.4792) -> (-23.4291, 51.5747)
extrude "31 mm parallel link (1)" add sketch "31 mm parallel link profile (1)" along normal blind 3 separate body makes body 6 in component "Left parallel links"
ref_plane "WorkPlane4" through (0, 0, -6) normal (0, 0, 1) x (1, 0, 0) in component "Left parallel links"
sketch "Pivot holes (1)" plane through (0, 0, -6) normal (0, 0, 1) x (1, 0, 0) in component "Left parallel links"
  circle A0 centre (-13.5, 22) radius 1.5
  circle A1 centre (-26.6012, 50.0955) radius 1.5
extrude "Through holes (1)" cut sketch "Pivot holes (1)" along normal blind 3 bodies 6 in component "Left parallel links"
sketch "Left link pivot axis" plane through (0, 0, 0) normal (0, 0, 1) x (1, 0, 0) in component "Frame - twin 3 mm plates"
  point P0 (-13.5, 22)
ref_plane "WorkPlane1" through (0, 0, -3) normal (0, 0, 1) x (1, 0, 0) in component "Left jaw - twin plates"
sketch "Jaw plate profile" plane through (0, 0, -3) normal (0, 0, 1) x (1, 0, 0) in component "Left jaw - twin plates"
  line L0 (-21.6012, 25.0955) -> (-31.6012, 25.0955)
  line L1 (-31.6012, 25.0955) -> (-31.6012, 53.0955)
  line L2 (-31.6012, 53.0955) -> (-12, 85.0955)
  line L3 (-12, 85.0955) -> (-3, 85.0955)
  line L4 (-3, 85.0955) -> (-3, 77.0955)
  line L5 (-3, 77.0955) -> (-11, 75.0955)
  line L6 (-11, 75.0955) -> (-21.6012, 49.0955)
  line L7 (-21.6012, 49.0955) -> (-21.6012, 25.0955)
extrude "Jaw plate" add sketch "Jaw plate profile" along normal blind 3 separate body makes body 7 in component "Left jaw - twin plates"
ref_plane "WorkPlane2" through (0, 0, -3) normal (0, 0, 1) x (1, 0, 0) in component "Left jaw - twin plates"
sketch "Pivot holes (4)" plane through (0, 0, -3) normal (0, 0, 1) x (1, 0, 0) in component "Left jaw - twin plates"
  circle A0 centre (-26.6012, 28.0955) radius 1.5
  circle A1 centre (-26.6012, 50.0955) radius 1.5
extrude "Through holes'''" cut sketch "Pivot holes (4)" along normal blind 3 bodies 7 in component "Left jaw - twin plates"
sketch "Jaw plate profile (1)" plane through (0, 0, 0) normal (0, 0, 1) x (1, 0, 0) in component "Left jaw - twin plates"
  line L0 (-21.6012, 25.0955) -> (-31.6012, 25.0955)
  line L1 (-31.6012, 25.0955) -> (-31.6012, 53.0955)
  line L2 (-31.6012, 53.0955) -> (-12, 85.0955)
  line L3 (-12, 85.0955) -> (-3, 85.0955)
  line L4 (-3, 85.0955) -> (-3, 77.0955)
  line L5 (-3, 77.0955) -> (-11, 75.0955)
  line L6 (-11, 75.0955) -> (-21.6012, 49.0955)
  line L7 (-21.6012, 49.0955) -> (-21.6012, 25.0955)
extrude "Jaw plate (1)" add sketch "Jaw plate profile (1)" along normal blind 3 separate body makes body 8 in component "Left jaw - twin plates"
sketch "Pivot holes (1) (2)" plane through (0, 0, 0) normal (0, 0, 1) x (1, 0, 0) in component "Left jaw - twin plates"
  circle A0 centre (-26.6012, 28.0955) radius 1.5
  circle A1 centre (-26.6012, 50.0955) radius 1.5
extrude "Through holes (1)'" cut sketch "Pivot holes (1) (2)" along normal blind 3 bodies 8 in component "Left jaw - twin plates"
sketch "Left crank to jaw axis" plane through (0, 0, 0) normal (0, 0, 1) x (1, 0, 0) in component "Left 24T gear and crank"
  point P0 (-26.6012, 28.0955)
sketch "Left follower to jaw axis" plane through (0, 0, 0) normal (0, 0, 1) x (1, 0, 0) in component "Left parallel links"
  point P0 (-26.6012, 50.0955)
ref_plane "WorkPlane1" through (0, 0, -6) normal (0, 0, 1) x (1, 0, 0) in component "Left lower crank"
sketch "Lower support link profile" plane through (0, 0, -6) normal (0, 0, 1) x (1, 0, 0) in component "Left lower crank"
  line L0 (-23.4291, 29.5747) -> (-23.92, 30.3453)
  line L1 (-23.92, 30.3453) -> (-24.5936, 30.9626)
  line L2 (-24.5936, 30.9626) -> (-25.4041, 31.3845)
  line L3 (-25.4041, 31.3845) -> (-26.2961, 31.5822)
  line L4 (-26.2961, 31.5822) -> (-27.2089, 31.5424)
  line L5 (-27.2089, 31.5424) -> (-28.0803, 31.2676)
  line L6 (-28.0803, 31.2676) -> (-28.8509, 30.7767)
  line L7 (-28.8509, 30.7767) -> (-29.4682, 30.1031)
  line L8 (-29.4682, 30.1031) -> (-29.8901, 29.2926)
  line L9 (-29.8901, 29.2926) -> (-30.0878, 28.4006)
  line L10 (-30.0878, 28.4006) -> (-30.048, 27.4878)
  line L11 (-30.048, 27.4878) -> (-29.7732, 26.6164)
  line L12 (-29.7732, 26.6164) -> (-16.6721, -1.4792)
  line L13 (-16.6721, -1.4792) -> (-16.1812, -2.2498)
  line L14 (-16.1812, -2.2498) -> (-15.5075, -2.867)
  line L15 (-15.5075, -2.867) -> (-14.6971, -3.2889)
  line L16 (-14.6971, -3.2889) -> (-13.805, -3.4867)
  line L17 (-13.805, -3.4867) -> (-12.8922, -3.4468)
  line L18 (-12.8922, -3.4468) -> (-12.0208, -3.1721)
  line L19 (-12.0208, -3.1721) -> (-11.2502, -2.6812)
  line L20 (-11.2502, -2.6812) -> (-10.633, -2.0075)
  line L21 (-10.633, -2.0075) -> (-10.2111, -1.1971)
  line L22 (-10.2111, -1.1971) -> (-10.0133, -0.305)
  line L23 (-10.0133, -0.305) -> (-10.0532, 0.6078)
  line L24 (-10.0532, 0.6078) -> (-10.3279, 1.4792)
  line L25 (-10.3279, 1.4792) -> (-23.4291, 29.5747)
extrude "Lower support link" add sketch "Lower support link profile" along normal blind 3 separate body makes body 9 in component "Left lower crank"
ref_plane "WorkPlane2" through (0, 0, -6) normal (0, 0, 1) x (1, 0, 0) in component "Left lower crank"
sketch "Pivot holes (5)" plane through (0, 0, -6) normal (0, 0, 1) x (1, 0, 0) in component "Left lower crank"
  circle A0 centre (-13.5, 0) radius 1.5
  circle A1 centre (-26.6012, 28.0955) radius 1.5
extrude "Through holes''''" cut sketch "Pivot holes (5)" along normal blind 3 bodies 9 in component "Left lower crank"
ref_plane "WorkPlane1" through (0, 0, -6) normal (0, 0, 1) x (1, 0, 0) in component "Left pivot pin 1"
sketch "Pivot shaft profile" plane through (0, 0, -6) normal (0, 0, 1) x (1, 0, 0) in component "Left pivot pin 1"
  circle A0 centre (-13.5, 0) radius 1.5
extrude "Pivot shaft" add sketch "Pivot shaft profile" along normal blind 12 separate body makes body 10 in component "Left pivot pin 1"
ref_plane "WorkPlane2" through (0, 0, 6) normal (0, 0, 1) x (1, 0, 0) in component "Left pivot pin 1"
sketch "Pin head profile" plane through (0, 0, 6) normal (0, 0, 1) x (1, 0, 0) in component "Left pivot pin 1"
  circle A0 centre (-13.5, 0) radius 2.5
extrude "Pin head" add sketch "Pin head profile" along normal blind 1 separate body makes body 11 in component "Left pivot pin 1"
ref_plane "WorkPlane3" through (0, 0, -7) normal (0, 0, 1) x (1, 0, 0) in component "Left pivot pin 1"
sketch "Pin retainer profile" plane through (0, 0, -7) normal (0, 0, 1) x (1, 0, 0) in component "Left pivot pin 1"
  circle A0 centre (-13.5, 0) radius 2.5
extrude "Pin retainer" add sketch "Pin retainer profile" along normal blind 1 separate body makes body 12 in component "Left pivot pin 1"
ref_plane "WorkPlane1" through (0, 0, -6) normal (0, 0, 1) x (1, 0, 0) in component "Left pivot pin 2"
sketch "Pivot shaft profile (2)" plane through (0, 0, -6) normal (0, 0, 1) x (1, 0, 0) in component "Left pivot pin 2"
  circle A0 centre (-13.5, 22) radius 1.5
extrude "Pivot shaft'" add sketch "Pivot shaft profile (2)" along normal blind 12 separate body makes body 13 in component "Left pivot pin 2"
ref_plane "WorkPlane2" through (0, 0, 6) normal (0, 0, 1) x (1, 0, 0) in component "Left pivot pin 2"
sketch "Pin head profile (2)" plane through (0, 0, 6) normal (0, 0, 1) x (1, 0, 0) in component "Left pivot pin 2"
  circle A0 centre (-13.5, 22) radius 2.5
extrude "Pin head'" add sketch "Pin head profile (2)" along normal blind 1 separate body makes body 14 in component "Left pivot pin 2"
ref_plane "WorkPlane3" through (0, 0, -7) normal (0, 0, 1) x (1, 0, 0) in component "Left pivot pin 2"
sketch "Pin retainer profile (2)" plane through (0, 0, -7) normal (0, 0, 1) x (1, 0, 0) in component "Left pivot pin 2"
  circle A0 centre (-13.5, 22) radius 2.5
extrude "Pin retainer'" add sketch "Pin retainer profile (2)" along normal blind 1 separate body makes body 15 in component "Left pivot pin 2"
ref_plane "WorkPlane1" through (0, 0, -6) normal (0, 0, 1) x (1, 0, 0) in component "Left pivot pin 3"
sketch "Pivot shaft profile (3)" plane through (0, 0, -6) normal (0, 0, 1) x (1, 0, 0) in component "Left pivot pin 3"
  circle A0 centre (-26.6012, 28.0955) radius 1.5
extrude "Pivot shaft''" add sketch "Pivot shaft profile (3)" along normal blind 12 separate body makes body 16 in component "Left pivot pin 3"
ref_plane "WorkPlane2" through (0, 0, 6) normal (0, 0, 1) x (1, 0, 0) in component "Left pivot pin 3"
sketch "Pin head profile (3)" plane through (0, 0, 6) normal (0, 0, 1) x (1, 0, 0) in component "Left pivot pin 3"
  circle A0 centre (-26.6012, 28.0955) radius 2.5
extrude "Pin head''" add sketch "Pin head profile (3)" along normal blind 1 separate body makes body 17 in component "Left pivot pin 3"
ref_plane "WorkPlane3" through (0, 0, -7) normal (0, 0, 1) x (1, 0, 0) in component "Left pivot pin 3"
sketch "Pin retainer profile (3)" plane through (0, 0, -7) normal (0, 0, 1) x (1, 0, 0) in component "Left pivot pin 3"
  circle A0 centre (-26.6012, 28.0955) radius 2.5
extrude "Pin retainer''" add sketch "Pin retainer profile (3)" along normal blind 1 separate body makes body 18 in component "Left pivot pin 3"
ref_plane "WorkPlane1" through (0, 0, -6) normal (0, 0, 1) x (1, 0, 0) in component "Left pivot pin 4"
sketch "Pivot shaft profile (4)" plane through (0, 0, -6) normal (0, 0, 1) x (1, 0, 0) in component "Left pivot pin 4"
  circle A0 centre (-26.6012, 50.0955) radius 1.5
extrude "Pivot shaft'''" add sketch "Pivot shaft profile (4)" along normal blind 12 separate body makes body 19 in component "Left pivot pin 4"
ref_plane "WorkPlane2" through (0, 0, 6) normal (0, 0, 1) x (1, 0, 0) in component "Left pivot pin 4"
sketch "Pin head profile (4)" plane through (0, 0, 6) normal (0, 0, 1) x (1, 0, 0) in component "Left pivot pin 4"
  circle A0 centre (-26.6012, 50.0955) radius 2.5
extrude "Pin head'''" add sketch "Pin head profile (4)" along normal blind 1 separate body makes body 20 in component "Left pivot pin 4"
ref_plane "WorkPlane3" through (0, 0, -7) normal (0, 0, 1) x (1, 0, 0) in component "Left pivot pin 4"
sketch "Pin retainer profile (4)" plane through (0, 0, -7) normal (0, 0, 1) x (1, 0, 0) in component "Left pivot pin 4"
  circle A0 centre (-26.6012, 50.0955) radius 2.5
extrude "Pin retainer'''" add sketch "Pin retainer profile (4)" along normal blind 1 separate body makes body 21 in component "Left pivot pin 4"
ref_plane "WorkPlane1" through (0, 0, 3) normal (0, 0, 1) x (1, 0, 0) in component "Right 24T gear and crank"